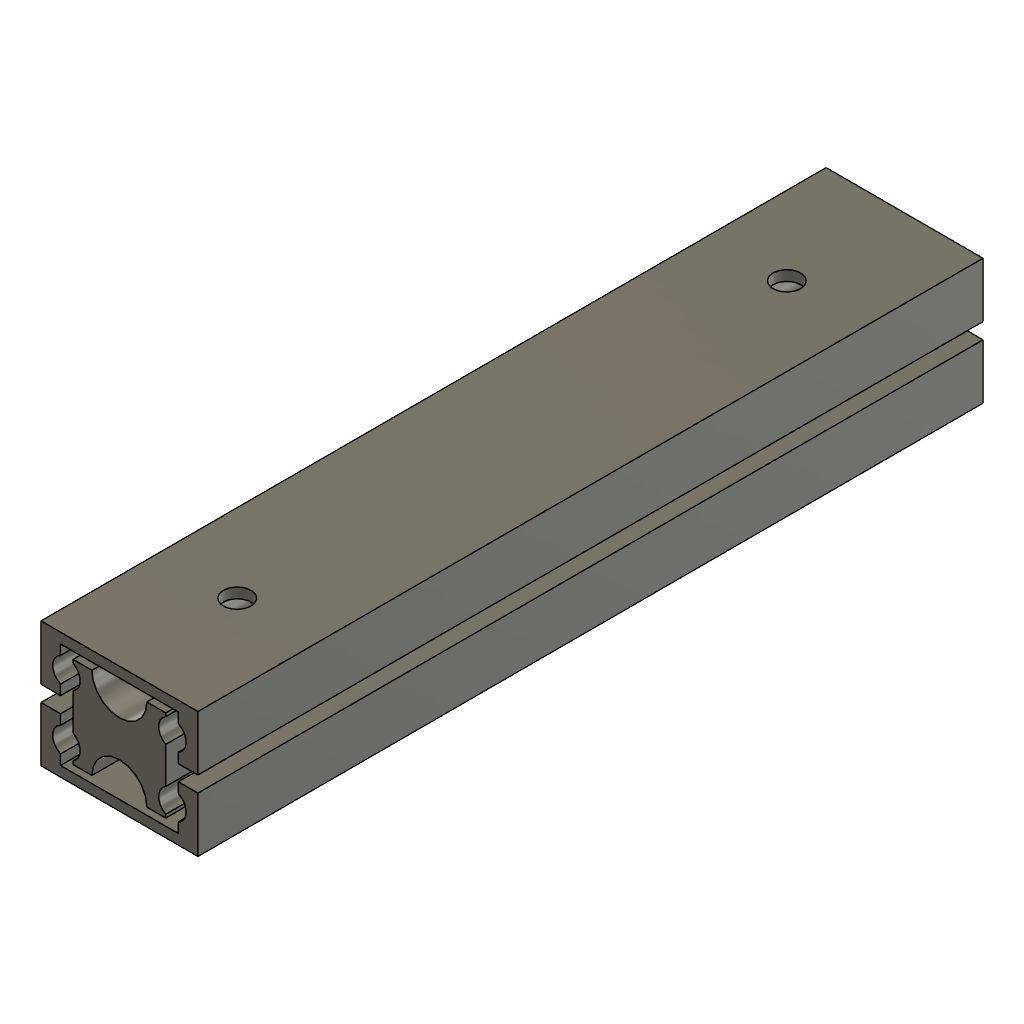
slider (Autodesk Fusion 360 design; units mm, degrees)
part number: 2026-11-13-23-38-29-931
part number: 2026-11-13-23-38-29-942
part number: 2026-11-13-23-38-29-944
Autodesk Fusion 360 part; units mm, degrees
sketch "草图1" plane through (0, 0, 0) normal (0, 0, 1) x (1, 0, 0)
  line L0 (10, -8) -> (-10, -8) construction
  line L1 (-10, -8) -> (-10, 8) construction
  line L2 (-10, 8) -> (10, 8) construction
  line L3 (10, 8) -> (10, -8) construction
  line L4 (10, -8) -> (-10, 8) construction
  line L5 (-10, -8) -> (10, 8) construction
  line L6 (5.9, -5.8) -> (-5.9, -5.8) construction
  line L7 (-5.9, -5.8) -> (-5.9, 5.8) construction
  line L8 (-5.9, 5.8) -> (5.9, 5.8) construction
  line L9 (5.9, 5.8) -> (5.9, -5.8) construction
  line L10 (5.9, -5.8) -> (-5.9, 5.8) construction
  line L11 (-5.9, -5.8) -> (5.9, 5.8) construction
  line L12 (-10, -8) -> (-10, -1)
  line L13 (-10, -1) -> (-7.5, -1)
  line L14 (-7.5, -1) -> (-7.5, -2.2689)
  line L15 (-7.5, -5.4311) -> (-7.5, -6.7)
  line L16 (-7.5, -6.7) -> (0, -6.7)
  line L17 (-10, 0) -> (10, 0) construction
  line L18 (0, 8) -> (0, -8) construction
  line L19 (-7.5, -1) -> (-7.5, -6.7) construction
  circle A0 centre (-6.75, -3.85) radius 1.75
  line L20 (-10, -8) -> (0, -8)
  line L21 (-5.9, -5.3797) -> (-5.9, -5.8)
  arc A1 (3.5, -5.8) -> (-3.5, -5.8) centre (0, -5.8) ccw
  line L22 (-3.5, -5.8) -> (-5.9, -5.8)
  line L23 (-5.9, -2.3203) -> (-5.9, 0)
  line L24 (-10, 1) -> (-7.5, 1)
  line L25 (-10, 8) -> (-10, 1)
  line L26 (-7.5, 1) -> (-7.5, 2.2689)
  circle A2 centre (-6.75, 3.85) radius 1.75
  line L27 (-7.5, 5.4311) -> (-7.5, 6.7)
  line L28 (-7.5, 6.7) -> (0, 6.7)
  line L29 (-10, 8) -> (0, 8)
  line L30 (-3.5, 5.8) -> (-5.9, 5.8)
  line L31 (-5.9, 5.3797) -> (-5.9, 5.8)
  line L32 (-5.9, 2.3203) -> (-5.9, 0)
  arc A3 (-3.5, 5.8) -> (3.5, 5.8) centre (0, 5.8) ccw
  line L33 (10, 8) -> (0, 8)
  line L34 (7.5, 6.7) -> (0, 6.7)
  line L35 (7.5, 5.4311) -> (7.5, 6.7)
  circle A4 centre (6.75, 3.85) radius 1.75
  line L36 (7.5, 1) -> (7.5, 2.2689)
  line L37 (10, 1) -> (7.5, 1)
  line L38 (10, 8) -> (10, 1)
  line L39 (10, -1) -> (7.5, -1)
  line L40 (10, -8) -> (10, -1)
  circle A5 centre (6.75, -3.85) radius 1.75
  line L41 (7.5, -1) -> (7.5, -2.2689)
  line L42 (7.5, -6.7) -> (0, -6.7)
  line L43 (7.5, -5.4311) -> (7.5, -6.7)
  line L44 (10, -8) -> (0, -8)
  line L45 (5.9, -5.3797) -> (5.9, -5.8)
  line L46 (5.9, -2.3203) -> (5.9, 0)
  line L47 (3.5, -5.8) -> (5.9, -5.8)
  line L48 (3.5, 5.8) -> (5.9, 5.8)
  line L49 (5.9, 2.3203) -> (5.9, 0)
  line L50 (5.9, 5.3797) -> (5.9, 5.8)
  point P0 (-7.5, -3.85)
  point P1 (-6.75, -3.85)
  dimension "d1" = 20
  dimension "d2" = 16
  dimension "d3" = 11.8
  dimension "d4" = 11.6
  dimension "d7" = 2.5
  dimension "d8" = 1
  dimension "d9" = 1.3
  dimension "d10" = 0.75
  dimension "d11" = 3.5
  dimension "d12" = 3.5
  constraint horizontal L0
  constraint perpendicular L0 L1
  constraint parallel L0 L2
  constraint parallel L1 L3
  constraint coincident L4 origin
  constraint coincident L5 origin
  constraint horizontal L6
  constraint perpendicular L6 L7
  constraint parallel L6 L8
  constraint parallel L7 L9
  constraint coincident L10 origin
  constraint coincident L11 origin
  constraint coincident L1 L12.end
  constraint perpendicular L1 L13
  constraint perpendicular L13 L14
  constraint perpendicular L13 L15
  constraint perpendicular L15 L16
  constraint midpoint L1 L17.start
  constraint midpoint L3 L17.end
  constraint midpoint L2 L18.start
  constraint midpoint L0 L18.end
  constraint collinear L14 L15
  constraint midpoint L19 P0
  constraint coincident P1 A0.centre
  constraint coincident L15.start A0
  constraint coincident L14.end A0
  constraint horizontal P0 P1
  constraint coincident A0 L21.start
  constraint coincident L7 L21.start
  constraint coincident L6 A1.start
  constraint midpoint L6 A1.centre
  constraint perpendicular L21 L22
  constraint coincident A0 L23.start
  constraint coincident L7 L23.start
  constraint midpoint L7 L23.end
  constraint symmetric L0.end L17 L1.end
  constraint symmetric L6.end L17 L7.end
  constraint symmetric L12.end L17 L24.start
  constraint symmetric L13.end L17 L24.end
  constraint symmetric L14.end L17 L26.end
  constraint symmetric L15.start L17 L27.start
  constraint symmetric L15.end L17 L27.end
  constraint symmetric L16.end L17 L28.end
  constraint symmetric L17 L18.end L18.start
  constraint symmetric L17 A0 A2
  constraint symmetric L17 L21.start L31.start
  constraint symmetric L17 A1.start A3.end
  constraint symmetric L17 A1.end L30.start
  constraint symmetric L17 A1 A3
  constraint symmetric L17 L23.start L32.start
  constraint symmetric L17 L23.end L32.end
  constraint symmetric L0.end L18 L0.start
  constraint symmetric L6.end L18 L6.start
  constraint symmetric L12.end L18 L39.start
  constraint symmetric L13.end L18 L39.end
  constraint symmetric L14.end L18 L41.end
  constraint symmetric L15.start L18 L43.start
  constraint symmetric L15.end L18 L42.start
  constraint symmetric L16.end L18 L42.end
  constraint symmetric L20.end L18 L44.end
  constraint symmetric L18 A0 A5
  constraint symmetric L18 L21.start L45.start
  constraint symmetric L18 A1.end A1.start
  constraint symmetric L18 L23.start L46.start
  constraint symmetric L18 L23.end L46.end
  constraint symmetric L18 L24.start L37.start
  constraint symmetric L18 L24.end L36.start
  constraint symmetric L18 L1.end L2.end
  constraint symmetric L18 L26.end L36.end
  constraint symmetric L18 A2 A4
  constraint symmetric L18 L27.start L35.start
  constraint symmetric L18 L27.end L34.start
  constraint symmetric L18 L28.end L34.end
  constraint symmetric L18 L29.end L33.end
  constraint symmetric L18 L30.start A3.end
  constraint symmetric L18 L7.end L8.end
  constraint symmetric L18 L31.start L50.start
  constraint symmetric L18 L32.start L49.start
  measures "d1" distance of L1.end L2.end
  measures "d2" distance of L0.end L1.end
  measures "d3" distance of L7.end L8.end
  measures "d4" distance of L6.end L7.end
  measures "d7" distance of L12 L14
  measures "d8" distance of L13 L17
  measures "d9" distance of L0 L16
  measures "d10" distance of P0 P1
  measures "d11" diameter of A0
  measures "d12" radius of A1
extrude "拉伸1" add sketch "草图1" along normal mid plane 100 contours L12 L13 L14 L15 L16 A0 L20 L39 L40 A5 L41 L42 L43 L44 | A0 L21 A1 L22 L23 A2 L30 L31 L32 A3 A4 A5 L45 L46 L47 L48 L49 L50 | L24 L25 L26 A2 L27 L28 L29 L33 L34 L35 A4 L36 L37 L38 makes body 1 at (3.3333, -8, 16.6667) makes body 2 at (-3.2889, -4.6029, 16.6667) makes body 3 at (-3.3333, 8, -16.6667) in component "双层款超窄20MM宽微型铝合金滑轨"
sketch "草图1 (2)" plane through (0, 0, 0) normal (0, 1, 0) x (1, 0, 0) in component "双层款超窄20MM宽微型铝合金滑轨"
  line L0 (-10, 50) -> (-10, -50)
  line L1 (-10, -50) -> (10, -50)
  line L2 (10, -50) -> (10, 50)
  line L3 (10, 50) -> (-10, 50)
  line L4 (0, 35) -> (0, -35) construction
  circle A0 centre (0, 35) radius 1.75
  line L5 (-10, 0) -> (10, 0) construction
  circle A1 centre (0, 35) radius 3.4
  circle A2 centre (0, -35) radius 1.75
  circle A3 centre (0, -35) radius 3.4
  dimension "d15" = 70
  dimension "d16" = 3.5
  dimension "d17" = 6.8
  constraint vertical L4
  constraint midpoint origin L4
  constraint coincident L4.start A0.centre
  constraint midpoint L0 L5.start
  constraint midpoint L2 L5.end
  constraint concentric A0 A1
  constraint symmetric A0 L5 A2
  constraint symmetric L5 A1 A3
  measures "d15" distance of L4.start L4.end
  measures "d16" diameter of A0
  measures "d17" diameter of A1
extrude "拉伸2" cut sketch "草图1 (2)" along normal mid plane 40 contours A0 | A2 bodies 1 3 in component "双层款超窄20MM宽微型铝合金滑轨"
extrude "拉伸3" cut sketch "草图1 (2)" along normal mid plane 20 contours A0 | A1 | A2 | A3 bodies 2 in component "双层款超窄20MM宽微型铝合金滑轨"
copy_body "实体->零部件1" bodies 1 removing the originals makes body 4 in component "下"
copy_body "实体->零部件2" bodies 2 removing the originals makes body 5 in component "中"
copy_body "实体->零部件3" bodies 3 removing the originals makes body 6 in component "上"
component "双层款超窄20MM宽微型铝合金滑轨" placed x (1, 0, 0) y (0, 1, 0) z (0, 0, 1) at (0, 0, 0)
component "下" placed x (1, 0, 0) y (0, 1, 0) z (0, 0, 1) at (0, 0, 0) in component "双层款超窄20MM宽微型铝合金滑轨"
component "中" placed x (1, 0, 0) y (0, 1, 0) z (0, 0, 1) at (0, 0, 0) in component "双层款超窄20MM宽微型铝合金滑轨"
component "上" placed x (1, 0, 0) y (0, 1, 0) z (0, 0, 1) at (0, 0, 0) in component "双层款超窄20MM宽微型铝合金滑轨"
equation "d13 = 总长"
equation "d15 = 孔距"
equation "总长 = 100 mm"
equation "孔距 = 70 mm"
